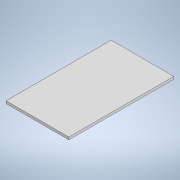
# Autodesk Inventor part: laterala_box_sertare
Saved by Autodesk Inventor 2022.6 (Build 266554000, 554)
## iProperties
Created: 2026-10-31
Part Number: laterala_box_sertare
Material: Generic
Document SubType Name: Modeling
Designer: Dragos Macovei
Density: 1 g/cm^3
Appearance: Default
Author: Dragos Macovei
Autodesk Inventor part; units mm, degrees
ref_plane "YZ Plane" through (0, 0, 0) normal (1, 0, 0) x (0, 1, 0)
ref_plane "XZ Plane" through (0, 0, 0) normal (0, 1, 0) x (-1, 0, 0)
ref_plane "XY Plane" through (0, 0, 0) normal (0, 0, 1) x (1, 0, 0)
sketch "Sketch1" plane through (0, 0, 0) normal (0, 1, 0) x (-1, 0, 0)
  line L0 (8.7421, 775.7936) -> (-451.2579, 775.7936)
  line L1 (-451.2579, 775.7936) -> (-451.2579, 5.7936)
  line L2 (-451.2579, 5.7936) -> (8.7421, 5.7936)
  line L3 (8.7421, 5.7936) -> (8.7421, 775.7936)
  point P0 (0, 0)
  dimension "d0" = 460
  dimension "d1" = 770
  constraints: 8 end point, 2 parallel, 1 horizontal, 1 perpendicular
  measures "d0" distance of L2.end L1.end
  measures "d1" distance of L2.end L0.start
extrude "Extrusion1" add sketch "Sketch1" along normal blind 18
body "Solid1"
